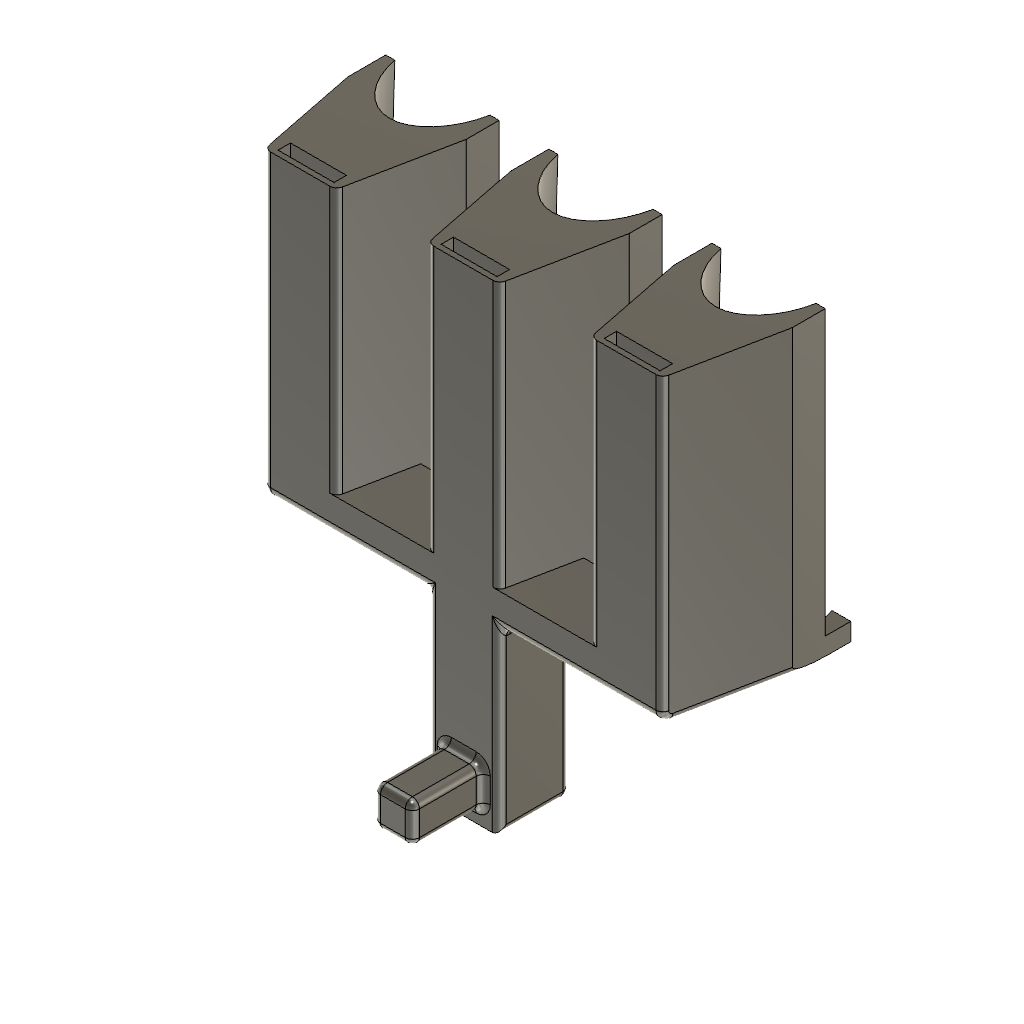
picus2_holder_3_middle (Autodesk Fusion 360 design; units mm, degrees)
Autodesk Fusion 360 part; units mm, degrees
sketch "スケッチ1" plane through (0, 0, 0) normal (0, 0, 1) x (1, 0, 0)
  line L0 (-11.79, 0) -> (11.79, 0)
  spline S0 degree 5 poles (-11.79, 0) (-11.7187, -1.0402) (-11.4537, -2.9893) (-10.6897, -5.5194) (-9.0102, -8.1364) (-6.1997, -10.2968) (-3.0791, -11.5077) (0, -11.894) (3.0791, -11.5077) (6.1997, -10.2968) (9.0102, -8.1364) (10.6897, -5.5194) (11.4537, -2.9893) (11.7187, -1.0402) (11.79, 0) knots 0 0 0 0 0 0 0.1 0.2 0.3 0.4 0.5 0.6 0.7 0.8 0.9 1 1 1 1 1 1
  line L1 (-12.0493, 3.7804) -> (-11.5307, -3.7804)
  line L2 (-2.2, -11.7) -> (2.2, -11.7)
  line L3 (11.5307, -3.7804) -> (12.0493, 3.7804)
  line L4 (-11.79, 0) -> (-11.79, 6) construction
  line L5 (11.79, 0) -> (11.79, 6) construction
  spline S1 degree 5 poles (11.79, 0) (11.79, 1.3573) (11.6696, 3.8152) (11.1279, 6.7317) (9.7203, 9.2043) (7.0275, 10.5816) (3.6813, 10.984) (0, 11.0253) (-3.6813, 10.984) (-7.0275, 10.5816) (-9.7203, 9.2043) (-11.1279, 6.7317) (-11.6696, 3.8152) (-11.79, 1.3573) (-11.79, 0) knots 0 0 0 0 0 0 0.1 0.2 0.3 0.4 0.5 0.6 0.7 0.8 0.9 1 1 1 1 1 1
  line L6 (-11.79, 5.2) -> (-11.79, -5.2)
  line L7 (11.79, -5.2) -> (11.79, 5.2)
  line L8 (0, -20) -> (0, 20) construction
  line L9 (16, 0) -> (-16, 0)
  line L10 (16, 0) -> (16, 7.2)
  line L11 (16, 7.2) -> (10.5751, 7.2)
  line L12 (-16, 0) -> (-16, 7.2)
  line L13 (-16, 7.2) -> (-10.5751, 7.2)
  point P0 (0, -11.7)
  point P1 (0, 11)
  dimension "d14" = 6
  dimension "d15" = 6
  dimension "d22" = 11.79
  dimension "d23" = 11.79
  dimension "d24" = 32
  dimension "d25" = 7.2
  constraint midpoint L0.start L1
  constraint midpoint L0.end L3
  constraint midpoint P0 L2
  constraint horizontal L0
  constraint coincident origin L0
  constraint perpendicular L0 L4
  constraint perpendicular L0 L5
  constraint midpoint L0.start L6
  constraint midpoint L0.end L7
  constraint vertical L8
  constraint coincident P1 L8
  constraint equal L1 L3
  constraint symmetric L1 L3 L8
  constraint equal L6 L7
  constraint symmetric L6 L7 L8
  constraint coincident L4 L6.start
  constraint perpendicular L6 L9
  constraint midpoint origin L9
  constraint perpendicular L9 L10
  constraint coincident S1 L11.end
  constraint perpendicular L10 L11
  constraint perpendicular L9 L12
  constraint coincident S1 L13.end
  constraint perpendicular L12 L13
  measures "d14" distance of L0.start L4.end
  measures "d15" distance of L0.end L5.end
  measures "d22" distance of origin L0.end
  measures "d23" distance of origin L0.start
  measures "d24" distance of L9.start L9.end
  measures "d25" distance of L9.start L10.end
ref_plane "作業平面1" through (0, 0, 55) normal (0, 0, 1) x (1, 0, 0)
sketch "スケッチ2" plane through (0, 0, 55) normal (0, 0, 1) x (1, 0, 0)
  spline S0 degree 5 poles (14.35, 0) (14.2202, -1.2627) (13.8473, -3.6749) (12.9477, -6.9534) (11.1026, -10.6374) (7.9173, -14.0361) (4.1165, -16.14) (0, -16.8583) (-4.1165, -16.14) (-7.9173, -14.0361) (-11.1026, -10.6374) (-12.9477, -6.9534) (-13.8473, -3.6749) (-14.2202, -1.2627) (-14.35, 0) knots 0 0 0 0 0 0 0.1 0.2 0.3 0.4 0.5 0.6 0.7 0.8 0.9 1 1 1 1 1 1
  line L0 (14.8175, 4.5484) -> (13.8825, -4.5484)
  line L1 (-13.8825, -4.5484) -> (-14.8175, 4.5484)
  line L2 (-14.35, 0) -> (14.35, 0)
  line L3 (0, -20) -> (0, 10) construction
  point P0 (0, -16.5)
  dimension "d16" = 14.35
  dimension "d17" = 14.35
  constraint midpoint S0.end L1
  constraint midpoint S0.start L0
  constraint horizontal L2
  constraint coincident origin L2
  constraint vertical L3
  constraint equal L0 L1
  constraint symmetric L0 L1 L3
  measures "d16" distance of origin S0.start
  measures "d17" distance of origin S0.end
ref_plane "作業平面2" through (0, -8.25, 85) normal (0, 0, 1) x (1, 0, 0)
sketch "スケッチ3" plane through (0, 0, 85) normal (0, 0, 1) x (1, 0, 0)
  spline S0 degree 5 poles (13.43, 0) (13.2221, -1.0368) (12.7223, -3.0465) (11.7204, -5.8695) (9.9059, -9.2149) (6.9862, -12.4962) (3.6101, -14.6245) (0, -15.3717) (-3.6101, -14.6245) (-6.9862, -12.4962) (-9.9059, -9.2149) (-11.7204, -5.8695) (-12.7223, -3.0465) (-13.2221, -1.0368) (-13.43, 0) knots 0 0 0 0 0 0 0.1 0.2 0.3 0.4 0.5 0.6 0.7 0.8 0.9 1 1 1 1 1 1
  line L0 (14.2151, 3.9155) -> (12.6449, -3.9155)
  line L1 (-12.6449, -3.9155) -> (-14.2151, 3.9155)
  line L2 (13.43, 0) -> (-13.43, 0)
  line L3 (7.9, -38.5) -> (-7.9, -38.5)
  line L4 (-7.9, -38.5) -> (-7.9, -35)
  line L5 (-7.9, -35) -> (7.9, -35)
  line L6 (7.9, -35) -> (7.9, -38.5)
  line L7 (0, 5) -> (0, -75) construction
  line L8 (-16, 0) -> (-16, -40)
  line L9 (-16, -40) -> (16, -40)
  line L10 (16, -40) -> (16, 0)
  line L11 (-16, -10.7058) -> (-10.1412, -40)
  line L12 (16, -9.2942) -> (9.8588, -40)
  line L13 (16, 0) -> (13.43, 0)
  line L14 (-13.43, 0) -> (-16, 0)
  line L15 (20, 0) -> (-20, 0) construction
  point P0 (0, -15)
  dimension "d3" = 15.8
  dimension "d4" = 3.5
  dimension "d5" = 20
  dimension "d18" = 13.43
  dimension "d19" = 13.43
  dimension "d20" = 2.57
  dimension "d21" = 2.57
  constraint coincident S0.end L2.end
  constraint midpoint S0.end L1
  constraint midpoint S0.start L0
  constraint coincident S0.start L2.start
  constraint coincident origin L2
  constraint horizontal L3
  constraint vertical L4
  constraint horizontal L5
  constraint vertical L6
  constraint symmetric L4 L6 L7
  constraint vertical L8
  constraint horizontal L9
  constraint vertical L10
  constraint coincident L8 L11.start
  constraint coincident L9 L11.end
  constraint coincident L10 L12.start
  constraint coincident L9 L12.end
  constraint horizontal L15
  constraint collinear L2 L15
  constraint coincident L8.start L15
  constraint coincident L10.end L15
  constraint coincident P0 L7
  constraint symmetric L0 L1 L7
  constraint equal L0 L1
  measures "d3" distance of L3.start L3.end
  measures "d4" distance of L3.start L5.end
  measures "d5" distance of P0 L5
  measures "d18" distance of origin S0.start
  measures "d19" distance of origin S0.end
  measures "d20" distance of S0.end L8.start
  measures "d21" distance of S0.start L10.end
extrude "押し出し1" add sketch "スケッチ3" against normal blind 85 contours S0 L8 L9 L10 L11 L12 L13 L14 | S0 L2 | L3 L4 L5 L6 makes body 1
extrude "押し出し2" cut sketch "スケッチ3" against normal blind 5 contours L3 L4 L5 L6 bodies 1
loft "ロフト1" add profiles "スケッチ3", "スケッチ2" section 1 contours S0 L2 section 2 separate body makes body 2
loft "ロフト2" add profiles "スケッチ2", "スケッチ1" section 1 section 2 contours L0 S0 L9 bodies 2
combine "結合1" operation cut target body 1 tool bodies 2
extrude "押し出し3" add sketch "スケッチ1" along normal blind 5 contours S1 L9 L12 L13 | S1 L9 L10 L11 bodies 1
fillet "フィレット1" radius 10 2 edges at (11.79, 0, 2.5) (-11.79, 0, 2.5) on bodies 1
sketch "スケッチ4" plane through (0, -40, 0) normal (0, -1, 0) x (1, 0, 0)
  line L0 (9.8588, 85) -> (-10.1412, 85)
  line L1 (-10.1412, 85) -> (-10.1412, 0)
  line L2 (-10.1412, 0) -> (9.8588, 0)
  line L3 (9.8588, 0) -> (9.8588, 85)
  line L4 (-5.5, 4.5) -> (5.5, 4.5)
  line L5 (5.5, 4.5) -> (5.5, 15.5)
  line L6 (5.5, 15.5) -> (-5.5, 15.5)
  line L7 (-5.5, 15.5) -> (-5.5, 4.5)
  line L8 (0, 0) -> (0, 95.5) construction
  point P0 (0, 4.5)
  dimension "d30" = 11
  dimension "d31" = 11
  dimension "d32" = 4.5
  constraint horizontal L4
  constraint vertical L5
  constraint horizontal L6
  constraint vertical L7
  constraint midpoint L4 P0
  constraint coincident L8.start origin
  constraint perpendicular L0 L8
  constraint coincident P0 L8
  measures "d30" distance of L4.start L4.end
  measures "d31" distance of L4.start L6.end
  measures "d32" distance of L8.start P0
copy_body "ボディのコピーと貼り付け1" bodies 1 makes body 3
move_body "移動1" bodies 3 to x (1, 0, 0) y (0, 1, 0) z (0, 0, 1) at (46, 0, 0)
copy_body "ボディのコピーと貼り付け2" bodies 1 makes body 4
move_body "移動2" bodies 4 to x (1, 0, 0) y (0, 1, 0) z (0, 0, 1) at (-46, 0, 0)
sketch "スケッチ5" plane through (0, -40, 0) normal (0, -1, 0) x (1, 0, 0)
  line L0 (9.8588, 85) -> (-10.1412, 85)
  line L1 (-10.1412, 85) -> (-10.1412, 0)
  line L2 (-10.1412, 0) -> (9.8588, 0)
  line L3 (9.8588, 0) -> (9.8588, 85)
  line L4 (-56.1412, 10) -> (55.8588, 10)
  line L5 (55.8588, 10) -> (55.8588, 0)
  line L6 (55.8588, 0) -> (-56.1412, 0)
  line L7 (-56.1412, 0) -> (-56.1412, 10)
  line L8 (-56.1412, 85) -> (-56.1412, 0)
  line L9 (55.8588, 85) -> (55.8588, 0)
  constraint horizontal L4
  constraint vertical L5
  constraint horizontal L6
  constraint vertical L7
  constraint collinear L7 L8
  constraint collinear L5 L9
extrude "押し出し5" add sketch "スケッチ5" against normal blind 20 contours L3 L4 L5 L6 L9 | L1 L2 L3 L4 L6 | L1 L4 L6 L7 L8 bodies 1 3 4
sketch "スケッチ6" plane through (0, -40, 0) normal (0, -1, 0) x (1, 0, 0)
  line L0 (55.8588, 0) -> (55.8588, 85)
  line L1 (55.8588, 85) -> (35.8588, 85)
  line L2 (35.8588, 85) -> (35.8588, 10)
  line L3 (35.8588, 10) -> (9.8588, 10)
  line L4 (9.8588, 10) -> (9.8588, 85)
  line L5 (9.8588, 85) -> (-10.1412, 85)
  line L6 (-10.1412, 85) -> (-10.1412, 10)
  line L7 (-10.1412, 10) -> (-36.1412, 10)
  line L8 (-36.1412, 10) -> (-36.1412, 85)
  line L9 (-36.1412, 85) -> (-56.1412, 85)
  line L10 (-56.1412, 85) -> (-56.1412, 0)
  line L11 (-56.1412, 0) -> (55.8588, 0)
  line L12 (5.5, 4.5) -> (-5.5, 4.5)
  line L13 (-5.5, 4.5) -> (-5.5, 15.5)
  line L14 (-5.5, 15.5) -> (5.5, 15.5)
  line L15 (5.5, 15.5) -> (5.5, 4.5)
  line L16 (5.5, 4.5) -> (-5.5, 15.5) construction
  line L17 (-5.5, 4.5) -> (5.5, 15.5) construction
  point P0 (0, 10)
  dimension "d43" = 11
  dimension "d44" = 11
  constraint horizontal L12
  constraint perpendicular L12 L13
  constraint parallel L12 L14
  constraint parallel L13 L15
  constraint coincident L16 P0
  constraint coincident L17 P0
  measures "d43" distance of L13.end L14.end
  measures "d44" distance of L12.end L13.end
sketch "スケッチ7" plane through (0, 0, 0) normal (0, 0, -1) x (1, 0, 0)
  line L0 (55.8588, 40) -> (-56.1412, 40)
  line L1 (-56.1412, 40) -> (-62, 10.7058)
  line L2 (-62, 10.7058) -> (-62, -7.2)
  line L3 (-62, -7.2) -> (-56.5751, -7.2)
  spline S0 degree 5 poles (-56.5751, -7.2) (-56.7197, -6.9065) (-57.1428, -5.9214) (-57.464, -4.7324) (-57.6758, -3.3153) (-57.7739, -1.6562) (-57.7877, -0.4118) knots 0.856217 0.856217 0.856217 0.856217 0.856217 0.856217 0.9 0.99386 0.99386 0.99386 0.99386 0.99386 0.99386
  spline S1 degree 3 poles (-57.7926, -0.0379) (-57.7926, -0.0462) (-57.7925, -0.0545) (-57.7921, -0.0961) (-57.7916, -0.1328) (-57.7902, -0.2342) (-57.7887, -0.3229) (-57.7877, -0.4118) knots 0.003792 0.003792 0.003792 0.003792 0.006286 0.006286 0.016309 0.016309 0.03855 0.03855 0.03855 0.03855
  spline S2 degree 3 poles (-34.2123, -0.4118) (-34.2106, -0.2587) (-34.208, -0.1446) (-34.2074, -0.0391) (-34.2074, -0.0385) (-34.2074, -0.0379) knots 0 0 0 0 0.045949 0.045949 0.046223 0.046223 0.046223 0.046223
  spline S3 degree 5 poles (-34.2123, -0.4118) (-34.2261, -1.6562) (-34.3242, -3.3153) (-34.536, -4.7324) (-34.8572, -5.9214) (-35.2803, -6.9065) (-35.4249, -7.2) knots 0.00614 0.00614 0.00614 0.00614 0.00614 0.00614 0.1 0.143783 0.143783 0.143783 0.143783 0.143783 0.143783
  line L4 (-35.4249, -7.2) -> (-30, -7.2)
  line L5 (-30, -7.2) -> (-30, 9.2942)
  line L6 (-30, 9.2942) -> (-32.1412, 20)
  line L7 (-32.1412, 20) -> (-14.1412, 20)
  line L8 (-14.1412, 20) -> (-16, 10.7058)
  line L9 (-16, 10.7058) -> (-16, -7.2)
  line L10 (-16, -7.2) -> (-10.5751, -7.2)
  spline S4 degree 5 poles (-10.5751, -7.2) (-10.7197, -6.9065) (-11.1428, -5.9214) (-11.464, -4.7324) (-11.6758, -3.3153) (-11.7739, -1.6562) (-11.7877, -0.4118) knots 0.856217 0.856217 0.856217 0.856217 0.856217 0.856217 0.9 0.99386 0.99386 0.99386 0.99386 0.99386 0.99386
  spline S5 degree 3 poles (-11.7926, -0.0379) (-11.7926, -0.0462) (-11.7925, -0.0545) (-11.7921, -0.0961) (-11.7916, -0.1328) (-11.7902, -0.2342) (-11.7887, -0.3229) (-11.7877, -0.4118) knots 0.003792 0.003792 0.003792 0.003792 0.006286 0.006286 0.016309 0.016309 0.03855 0.03855 0.03855 0.03855
  spline S6 degree 3 poles (11.7877, -0.4118) (11.7894, -0.2587) (11.792, -0.1446) (11.7926, -0.0391) (11.7926, -0.0385) (11.7926, -0.0379) knots 0 0 0 0 0.045949 0.045949 0.046223 0.046223 0.046223 0.046223
  spline S7 degree 5 poles (11.7877, -0.4118) (11.7739, -1.6562) (11.6758, -3.3153) (11.464, -4.7324) (11.1428, -5.9214) (10.7197, -6.9065) (10.5751, -7.2) knots 0.00614 0.00614 0.00614 0.00614 0.00614 0.00614 0.1 0.143783 0.143783 0.143783 0.143783 0.143783 0.143783
  line L11 (10.5751, -7.2) -> (16, -7.2)
  line L12 (16, -7.2) -> (16, 9.2942)
  line L13 (16, 9.2942) -> (13.8588, 20)
  line L14 (13.8588, 20) -> (31.8588, 20)
  line L15 (31.8588, 20) -> (30, 10.7058)
  line L16 (30, 10.7058) -> (30, -7.2)
  line L17 (30, -7.2) -> (35.4249, -7.2)
  spline S8 degree 5 poles (35.4249, -7.2) (35.2803, -6.9065) (34.8572, -5.9214) (34.536, -4.7324) (34.3242, -3.3153) (34.2261, -1.6562) (34.2123, -0.4118) knots 0.856217 0.856217 0.856217 0.856217 0.856217 0.856217 0.9 0.99386 0.99386 0.99386 0.99386 0.99386 0.99386
  spline S9 degree 3 poles (34.2074, -0.0379) (34.2074, -0.0462) (34.2075, -0.0545) (34.2079, -0.0961) (34.2084, -0.1328) (34.2098, -0.2342) (34.2113, -0.3229) (34.2123, -0.4118) knots 0.003792 0.003792 0.003792 0.003792 0.006286 0.006286 0.016309 0.016309 0.03855 0.03855 0.03855 0.03855
  spline S10 degree 3 poles (57.7877, -0.4118) (57.7894, -0.2587) (57.792, -0.1446) (57.7926, -0.0391) (57.7926, -0.0385) (57.7926, -0.0379) knots 0 0 0 0 0.045949 0.045949 0.046223 0.046223 0.046223 0.046223
  spline S11 degree 5 poles (57.7877, -0.4118) (57.7739, -1.6562) (57.6758, -3.3153) (57.464, -4.7324) (57.1428, -5.9214) (56.7197, -6.9065) (56.5751, -7.2) knots 0.00614 0.00614 0.00614 0.00614 0.00614 0.00614 0.1 0.143783 0.143783 0.143783 0.143783 0.143783 0.143783
  line L18 (56.5751, -7.2) -> (62, -7.2)
  line L19 (62, -7.2) -> (62, 9.2942)
  line L20 (62, 9.2942) -> (55.8588, 40)
  line L21 (-10, 40) -> (10, 40)
  line L22 (10, 40) -> (10, 20)
  line L23 (10, 20) -> (-10, 20)
  line L24 (-10, 20) -> (-10, 40)
  line L25 (-57.79, 0) -> (-57.7926, -0.0379)
  spline S12 degree 3 poles (-57.79, 0) (-57.5796, 3.0673) (-56.6973, 5.4368) (-55.3716, 7.1994) (-54.0131, 9.0056) (-52.2198, 10.1867) (-50.371, 10.8902) (-49.1132, 11.3688) (-47.8353, 11.6268) (-46.5675, 11.6866) (-44.8632, 11.7671) (-43.1431, 11.4939) (-41.4561, 10.8229) (-39.1882, 9.9208) (-37.0196, 8.2907) (-35.6615, 5.6554) (-34.8718, 4.1229) (-34.3641, 2.2474) (-34.21, 0) knots -1 -1 -1 -1 -0.823071 -0.823071 -0.823071 -0.641766 -0.641766 -0.641766 -0.51841 -0.51841 -0.51841 -0.352575 -0.352575 -0.352575 -0.129637 -0.129637 -0.129637 0 0 0 0
  line L26 (-34.2074, -0.0379) -> (-34.21, 0)
  line L27 (-11.79, 0) -> (-11.7926, -0.0379)
  spline S13 degree 3 poles (-11.79, 0) (-11.5796, 3.0673) (-10.6973, 5.4368) (-9.3716, 7.1994) (-8.0131, 9.0056) (-6.2198, 10.1867) (-4.371, 10.8902) (-3.1132, 11.3688) (-1.8353, 11.6268) (-0.5675, 11.6866) (1.1368, 11.7671) (2.8569, 11.4939) (4.5439, 10.8229) (6.8118, 9.9208) (8.9804, 8.2907) (10.3385, 5.6554) (11.1282, 4.1229) (11.6359, 2.2474) (11.79, 0) knots -1 -1 -1 -1 -0.823071 -0.823071 -0.823071 -0.641766 -0.641766 -0.641766 -0.51841 -0.51841 -0.51841 -0.352575 -0.352575 -0.352575 -0.129637 -0.129637 -0.129637 0 0 0 0
  line L28 (11.7926, -0.0379) -> (11.79, 0)
  line L29 (34.21, 0) -> (34.2074, -0.0379)
  spline S14 degree 3 poles (34.21, 0) (34.4204, 3.0673) (35.3027, 5.4368) (36.6284, 7.1994) (37.9869, 9.0056) (39.7802, 10.1867) (41.629, 10.8902) (42.8868, 11.3688) (44.1647, 11.6268) (45.4325, 11.6866) (47.1368, 11.7671) (48.8569, 11.4939) (50.5439, 10.8229) (52.8118, 9.9208) (54.9804, 8.2907) (56.3385, 5.6554) (57.1282, 4.1229) (57.6359, 2.2474) (57.79, 0) knots -1 -1 -1 -1 -0.823071 -0.823071 -0.823071 -0.641766 -0.641766 -0.641766 -0.51841 -0.51841 -0.51841 -0.352575 -0.352575 -0.352575 -0.129637 -0.129637 -0.129637 0 0 0 0
  line L30 (57.7926, -0.0379) -> (57.79, 0)
  dimension "d53" = 20
  dimension "d54" = 20
  constraint horizontal L21
  constraint vertical L22
  constraint horizontal L23
  constraint vertical L24
  constraint coincident L0 L21.start
  measures "d53" distance of L21.start L21.end
  measures "d54" distance of L21.start L23.end
extrude "押し出し7" add sketch "スケッチ7" along normal blind 50 contours L0 L21 L22 L23 L24 bodies 1
sketch "スケッチ8" plane through (0, -40, 0) normal (0, -1, 0) x (1, 0, 0)
  line L0 (55.8588, 0) -> (55.8588, 85)
  line L1 (55.8588, 85) -> (35.8588, 85)
  line L2 (35.8588, 85) -> (35.8588, 10)
  line L3 (35.8588, 10) -> (9.8588, 10)
  line L4 (9.8588, 10) -> (9.8588, 85)
  line L5 (9.8588, 85) -> (-10.1412, 85)
  line L6 (-10.1412, 85) -> (-10.1412, 10)
  line L7 (-10.1412, 10) -> (-36.1412, 10)
  line L8 (-36.1412, 10) -> (-36.1412, 85)
  line L9 (-36.1412, 85) -> (-56.1412, 85)
  line L10 (-56.1412, 85) -> (-56.1412, 0)
  line L11 (-56.1412, 0) -> (-10, 0)
  line L12 (-10, 0) -> (-10, -50)
  line L13 (-10, -50) -> (10, -50)
  line L14 (10, -50) -> (10, 0)
  line L15 (10, 0) -> (55.8588, 0)
  line L16 (5.5, -45.5) -> (-5.5, -45.5)
  line L17 (-5.5, -45.5) -> (-5.5, -34.5)
  line L18 (-5.5, -34.5) -> (5.5, -34.5)
  line L19 (5.5, -34.5) -> (5.5, -45.5)
  line L20 (5.5, -45.5) -> (-5.5, -34.5) construction
  line L21 (-5.5, -45.5) -> (5.5, -34.5) construction
  point P0 (0, -40)
  dimension "d57" = 11
  dimension "d58" = 11
  constraint horizontal L16
  constraint perpendicular L16 L17
  constraint parallel L16 L18
  constraint parallel L17 L19
  constraint coincident L20 P0
  constraint coincident L21 P0
  measures "d57" distance of L17.end L18.end
  measures "d58" distance of L16.end L17.end
extrude "押し出し8" add sketch "スケッチ8" along normal blind 20 contours L16 L17 L18 L19 bodies 1
fillet "フィレット6" radius 3 2 edges at (-33.0706, -40, 0) (32.9294, -40, 0) on bodies 1
fillet "フィレット7" radius 2 10 edges at (-56.1412, -40, 44) (-56.3169, -39.1213, 0.8787) (-59.3706, -23.8529, 0) (-36.1412, -40, 47.5) (-10.1412, -40, 47.5) (9.8588, -40, 47.5) (35.8588, -40, 47.5) (55.8588, -40, 44) (56.0346, -39.1213, 0.8787) (59.2294, -23.1471, 0) on bodies 1
fillet "フィレット8" radius 2 4 faces at (5.5, -53.3333, -38.1667) (1.8333, -53.3333, -45.5) (-1.8333, -53.3333, -34.5) (-5.5, -53.3333, -41.8333) on bodies 1
fillet "フィレット9" radius 2 3 faces at (-10, -32.3333, -33.3333) (10, -32.3333, -33.3333) (3.3333, -20, -16.6667) on bodies 1
named bodies: "ピペットホールド治具", "ピペット側切り抜き", "ピペットホールド治具 (1)", "ピペットホールド治具 (1) (1)"
